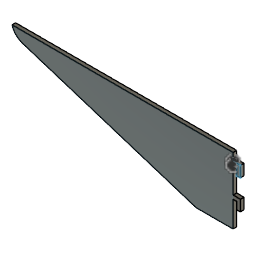
Gondola - Hook (Autodesk Fusion 360 design; units mm, degrees)
Autodesk Fusion 360 part; units mm, degrees
sketch "Sketch1" plane through (0, 0, 0) normal (0, 1, 0) x (1, 0, 0)
  line L0 (0, 0) -> (300, 0)
  line L1 (300, 0) -> (300, 90)
  line L2 (300, 90) -> (250, 90)
  line L3 (250, 90) -> (0, 10)
  line L4 (0, 10) -> (0, 0)
  arc A0 (14.162, 14.5318) -> (0, 0) centre (20.7497, -6.055) ccw
  dimension "d1" = 300
  constraint coincident L0.start L4.end
  constraint horizontal L0
  constraint perpendicular L0 L1
  constraint perpendicular L1 L2
  constraint perpendicular L0 L4
  constraint tangent L3 A0
  constraint coincident L3 A0.start
  measures "d1" distance of L0.start L0.end
extrude "Extrude1" add sketch "Sketch1" along normal blind 5 contours L0 L1 L2 L3 A0
sketch "Sketch2" plane through (0, 0, 0) normal (0, -1, 0) x (1, 0, 0)
  arc A0 (0, 0) -> (14.162, -14.5318) centre (20.7497, 6.055) ccw
  line L0 (14.162, -14.5318) -> (250, -90)
  line L1 (250, -90) -> (300, -90)
  line L2 (300, -90) -> (300, 0)
  line L3 (300, 0) -> (0, 0)
  line L4 (300, -10) -> (310, -10)
  line L5 (310, -10) -> (310, -25)
  line L6 (310, -25) -> (305, -25)
  line L7 (305, -25) -> (305, -15)
  line L8 (305, -15) -> (300, -15)
  constraint coincident L2 L4.start
  constraint perpendicular L2 L4
  constraint perpendicular L4 L5
  constraint perpendicular L5 L6
  constraint perpendicular L6 L7
  constraint coincident L2 L8.end
  constraint perpendicular L2 L8
extrude "Extrude2" add sketch "Sketch2" against normal blind 5 contours L2 L4 L5 L6 L7 L8
sketch "Sketch3" plane through (0, 0, 0) normal (0, -1, 0) x (1, 0, 0)
  line L0 (300, -50) -> (310, -50)
  line L1 (310, -50) -> (310, -65)
  line L2 (310, -65) -> (300, -65)
  line L3 (300, -65) -> (300, -50)
  line L4 (300, -65) -> (305, -65)
  line L5 (305, -65) -> (305, -55)
  line L6 (305, -55) -> (300, -55)
  line L7 (300, -55) -> (300, -65)
  dimension "d6" = 10
  constraint horizontal L0
  constraint vertical L1
  constraint horizontal L2
  constraint vertical L3
  constraint horizontal L4
  constraint vertical L5
  constraint horizontal L6
  constraint vertical L7
  measures "d6" distance of L0.start L0.end
extrude "Extrude3" add sketch "Sketch3" against normal blind 5 contours L0 L1 L2 L3 L5 L6
